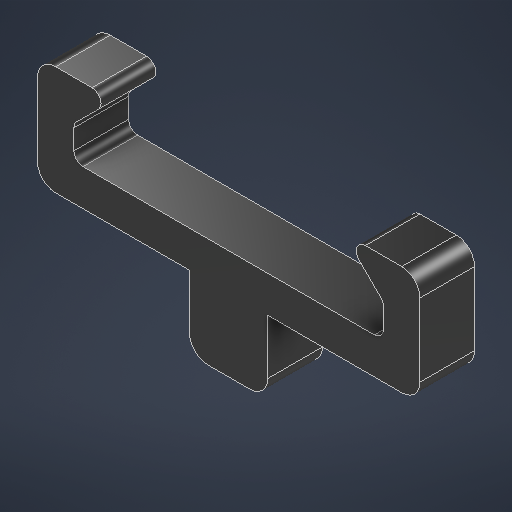
# Autodesk Inventor part: Laser Rx Slot
Saved by Autodesk Inventor 2027.1 (Build 311270010, 270A)
## iProperties
Created: 2026-10-18
Part Number: Laser Rx Slot
Material: MDF Medium Density Fiberboard
Document SubType Name: Modeling
Designer: Ahmed
Density: 0.8 g/cm^3
Appearance: Glossy - Black
Mass: 0.178206 g
Surface Area: 3.48613 cm^2
Volume: 0.222757 cm^3
Author: Ahmed
Autodesk Inventor part; units mm, degrees
ref_plane "YZ Plane" through (0, 0, 0) normal (1, 0, 0) x (0, 1, 0)
ref_plane "XZ Plane" through (0, 0, 0) normal (0, 1, 0) x (-1, 0, 0)
ref_plane "XY Plane" through (0, 0, 0) normal (0, 0, 1) x (1, 0, 0)
sketch "Sketch1" plane through (0, 0, 0) normal (0, 0, 1) x (1, 0, 0)
  line L0 (-8.5, 0) -> (8.5, 0)
  line L1 (-8.5, 0) -> (-8.5, 1.8)
  line L2 (8.5, 0) -> (8.5, 1.8)
  line L3 (-8.5, 1.8) -> (-6.3, 4)
  line L4 (-8.5, 1.8) -> (-5.3887, 1.8) construction
  line L5 (-6.3, 4) -> (-10.5, 4)
  line L6 (-10.5, 4) -> (-10.5, 0)
  line L7 (-10.5, 0) -> (-8.5, 0)
  line L8 (0, -1) -> (0, 1) construction
  line L9 (8.5, 1.8) -> (6.3, 4)
  line L10 (6.3, 4) -> (10.5, 4)
  line L11 (10.5, 4) -> (10.5, 0)
  line L12 (10.5, 0) -> (8.5, 0)
  line L13 (-10.5, 0) -> (10.5, 0)
  line L14 (10.5, 0) -> (10.5, -2)
  line L15 (10.5, -2) -> (-10.5, -2)
  line L16 (-10.5, -2) -> (-10.5, 0)
  line L17 (-2.15, -2) -> (2.15, -2)
  line L18 (2.15, -2) -> (2.15, -6)
  line L19 (2.15, -6) -> (-2.15, -6)
  line L20 (-2.15, -6) -> (-2.15, -2)
  point P0 (0, 0)
  point P1 (10.5, 0)
  point P2 (0, -2)
  point P3 (2.15, -2)
  point P4 (-2.15, -2)
  dimension "d0" = 17
  dimension "d1" = 1.8
  dimension "d3" = 45
  dimension "d4" = 2
  dimension "d5" = 2
  dimension "d6" = 2
  dimension "d7" = 2
  dimension "d10" = 4.3
  dimension "d11" = 4
  dimension "d12" = 6
  constraints: 42 end point, 5 horizontal, 5 perpendicular, 4 midpoint, 4 parallel, 3 symmetric about line, 3 vertical, 1 equal length
  measures "d0" distance of L0.start L0.end
  measures "d1" distance of L0.start L1.end
  measures "d3" angle of L4 L3
  measures "d4" distance of L6.end L0.start
  measures "d5" distance of L8.start L8.end
  measures "d6" distance of L13.end L14.end
  measures "d7" distance between parallel lines of L14 L2
  measures "d10" distance of L18.end L19.end
  measures "d11" distance of L17.end L18.end
  measures "d12" distance between parallel lines of L15 L10
extrude "Extrusion1" add sketch "Sketch1" along normal blind 3
fillet "Fillet1" radius 1 6 edges at (10.5, 4, 1.5) (10.5, -2, 1.5) (2.15, -6, 1.5) (-2.15, -6, 1.5) (-10.5, -2, 1.5) (-10.5, 4, 1.5)
fillet "Fillet2" radius 0.5 6 edges at (-6.3, 4, 1.5) (6.3, 4, 1.5) (8.5, 1.8, 1.5) (8.5, 0, 1.5) (-8.5, 1.8, 1.5) (-8.5, 0, 1.5)
equation "\"d1\" = RxThickness"
equation "\"GridProcutClearance\" = 5"
equation "\"GridBorderThickness\" = 5"
equation "\"GridBorderFillets\" = 7"
equation "\"GridTotalSize\" = 65"
equation "\"GridRobotClearance\" = 65"
equation "\"AluminiumExtrusionClearance\" = 35"
equation "\"BaseTotalLength\" = 885"
equation "\"WorkspaceLength\" = 515"
equation "\"WorkspaceHeight\" = 183"
equation "\"AxesBaseFillet\" = 15"
equation "\"Zaxis\" = 197"
equation "\"ProductTotalHeight\" = 45"
equation "\"VerticalStroke\" = 105"
equation "\"BackArea\" = 165"
equation "\"CylinderStroke\" = 75"
equation "\"BoxesWidth\" = 125"
equation "\"BaseWoodThickness\" = 7"
equation "\"Kerf\" = 0.3"
equation "\"RxThickness\" = 1.8"
equation "\"support_2\" = 265"
body "Solid1"
